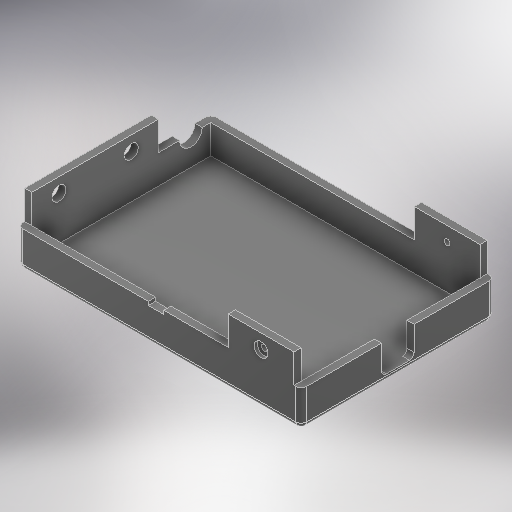
# Autodesk Inventor part: top_casing
Saved by Autodesk Inventor 2027 (Build 310192060, 192F)
## iProperties
Created: 2026-09-12
Part Number: top_casing
Material: Generic
Document SubType Name: Modeling
Designer: Aiden
Density: 1 g/cm^3
Appearance: Smooth - Black
Author: Aiden
Autodesk Inventor part; units mm, degrees
ref_plane "YZ Plane" through (0, 0, 0) normal (1, 0, 0) x (0, 1, 0)
ref_plane "XZ Plane" through (0, 0, 0) normal (0, 1, 0) x (-1, 0, 0)
ref_plane "XY Plane" through (0, 0, 0) normal (0, 0, 1) x (1, 0, 0)
sketch "Sketch1" plane through (0, 0, 0) normal (0, 1, 0) x (-1, 0, 0)
  line L0 (0, 0) -> (54.318, 0)
  line L1 (54.318, 0) -> (54.318, -54.318)
  line L2 (54.318, -54.318) -> (0, -54.318)
  line L3 (0, -54.318) -> (0, 0)
  line L4 (54.318, 0) -> (79.718, 0)
  line L5 (79.718, 0) -> (79.718, -54.318)
  line L6 (79.718, -54.318) -> (54.318, -54.318)
  line L7 (54.318, -54.318) -> (54.318, 0)
  dimension "d0" = 54.318
  dimension "d1" = 54.318
  dimension "d2" = 25.4
  constraints: 16 end point, 4 parallel, 2 horizontal, 2 perpendicular
  measures "d0" distance of L0.end L1.end
  measures "d1" distance of L1.end L2.end
  measures "d2" distance of L5.end L6.end
extrude "Extrusion1" add sketch "Sketch1" along normal blind 10.16
sketch "Sketch2" plane through (0, 10.16, 0) normal (0, 1, 0) x (1, 0, 0)
  line L0 (-77.686, 52.286) -> (-2.032, 52.286)
  line L1 (-2.032, 52.286) -> (-2.032, 2.032)
  line L2 (-2.032, 2.032) -> (-77.686, 2.032)
  line L3 (-77.686, 2.032) -> (-77.686, 52.286)
  line L4 (-77.686, 52.286) -> (-77.686, 54.318) construction
  line L5 (0, 54.318) -> (-79.718, 54.318) construction
  line L6 (-2.032, 52.286) -> (0, 52.286) construction
  line L7 (-2.032, 2.032) -> (-2.032, 0) construction
  line L8 (-79.718, 0) -> (0, 0) construction
  line L9 (-77.686, 2.032) -> (-79.718, 2.032) construction
  line L10 (-79.718, 54.318) -> (-79.718, 0) construction
  line L11 (0, 0) -> (0, 54.318) construction
  dimension "d5" = 2.032
  constraints: 16 end point, 6 perpendicular, 4 point on line, 2 parallel, 2 vertical, 1 horizontal
  measures "d5" distance of L0.start L4.end
extrude "Extrusion2" cut sketch "Sketch2" against normal blind 8.128
sketch "Sketch3" plane through (0, 10.16, 0) normal (0, 1, 0) x (1, 0, 0)
  line L0 (-2.032, 2.032) -> (-77.686, 2.032) projected
  line L1 (-79.718, 0) -> (0, 0) projected
  line L2 (-42.926, 2.032) -> (-38.608, 2.032)
  line L3 (-38.608, 2.032) -> (-38.608, 0)
  line L4 (-38.608, 0) -> (-42.926, 0)
  line L5 (-42.926, 0) -> (-42.926, 2.032)
  line L6 (0, 0) -> (0, 54.318) projected
  point P0 (-38.608, 1.016)
  dimension "d8" = 4.318
  dimension "d9" = 38.608
  constraints: 8 end point, 2 parallel, 2 point on line, 1 horizontal, 1 midpoint, 1 perpendicular
  measures "d8" distance from line of point (-38.608, 1.016) L5
  measures "d9" distance between parallel lines of L6 L3
extrude "Extrusion3" cut sketch "Sketch3" against normal blind 1.016
sketch "Sketch4" plane through (-79.718, 0, -54.318) normal (-1, 0, 0) x (0, 0, 1)
  circle A0 centre (7.62, 10.16) radius 3.175
  line L0 (0, 0) -> (0, 10.16) projected
  line L1 (0, 10.16) -> (54.318, 10.16) projected
  point P0 (54.318, 0)
  dimension "d12" = 6.35
  dimension "d13" = 7.62
  constraints: 1 centre point, 1 point on line
  measures "d12" diameter of A0
  measures "d13" distance from line of L0 A0.centre
extrude "Extrusion4" cut sketch "Sketch4" against normal blind 2.032
sketch "Sketch5" plane through (0, 10.16, 0) normal (0, 1, 0) x (1, 0, 0)
  line L0 (-42.926, 2.032) -> (-77.686, 2.032) projected
  line L1 (-79.718, 43.523) -> (-79.718, 0) projected
  line L2 (-77.686, 2.032) -> (-79.718, 2.032)
  line L3 (-79.718, 2.032) -> (-79.718, 37.592)
  line L4 (-79.718, 37.592) -> (-77.686, 37.592)
  line L5 (-77.686, 37.592) -> (-77.686, 2.032)
  point P0 (0, 0)
  dimension "d16" = 35.56
  constraints: 8 end point, 2 parallel, 1 horizontal, 1 perpendicular, 1 point on line
  measures "d16" distance between parallel lines of L2 L4
extrude "Extrusion5" add sketch "Sketch5" along normal blind 8.128
sketch "Sketch6" plane through (-79.718, 0, -54.318) normal (-1, 0, 0) x (0, 0, 1)
  line L0 (16.726, 18.288) -> (52.286, 18.288) projected
  line L1 (54.318, 10.16) -> (0, 10.16) projected
  line L2 (21.806, 18.288) -> (26.886, 18.288)
  line L3 (26.886, 18.288) -> (26.886, 10.16)
  line L4 (26.886, 10.16) -> (21.806, 10.16)
  line L5 (21.806, 10.16) -> (21.806, 18.288)
  line L6 (42.126, 10.16) -> (47.206, 10.16)
  line L7 (47.206, 10.16) -> (47.206, 18.288)
  line L8 (47.206, 18.288) -> (42.126, 18.288)
  line L9 (42.126, 18.288) -> (42.126, 10.16)
  line L10 (21.806, 14.224) -> (26.886, 14.224) construction
  line L11 (42.126, 14.224) -> (47.206, 14.224) construction
  line L12 (16.726, 10.16) -> (16.726, 18.288) construction
  line L13 (24.346, 18.288) -> (24.346, 10.16) construction
  line L14 (44.666, 10.16) -> (44.666, 18.288) construction
  line L15 (52.286, 10.16) -> (52.286, 18.288) construction
  circle A0 centre (24.346, 14.224) radius 1.95
  circle A1 centre (44.666, 14.224) radius 1.95
  point P0 (54.318, 0)
  dimension "d19" = 5.08
  dimension "d20" = 5.08
  dimension "d21" = 5.08
  dimension "d22" = 3.9
  constraints: 24 end point, 10 midpoint, 4 parallel, 4 point on line, 2 centre point, 2 horizontal, 2 perpendicular, 1 collinear, 1 equal radius
  measures "d19" distance of L10.start L10.end
  measures "d20" distance between parallel lines of L12 L5
  measures "d21" distance between parallel lines of L15 L7
  measures "d22" diameter of A0
extrude "Extrusion6" cut sketch "Sketch6" against normal blind 2.032 contours A0 | A1
sketch "Sketch7" plane through (0, 10.16, 0) normal (0, 1, 0) x (1, 0, 0)
  line L0 (-2.032, 2.032) -> (-77.686, 2.032) projected
  line L1 (-79.718, 0) -> (0, 0) projected
  line L2 (-20.5232, 2.032) -> (-2.032, 2.032)
  line L3 (-2.032, 2.032) -> (-2.032, 0)
  line L4 (-2.032, 0) -> (-20.5232, 0)
  line L5 (-20.5232, 0) -> (-20.5232, 2.032)
  line L6 (-77.686, 52.286) -> (-2.032, 52.286) projected
  line L7 (0, 54.318) -> (-79.718, 54.318) projected
  line L8 (-2.032, 52.286) -> (-20.5232, 52.286)
  line L9 (-20.5232, 52.286) -> (-20.5232, 54.318)
  line L10 (-20.5232, 54.318) -> (-2.032, 54.318)
  line L11 (-2.032, 54.318) -> (-2.032, 52.286)
  line L12 (0, 0) -> (0, 54.318) projected
  line L13 (-2.032, 1.016) -> (-20.5232, 1.016) construction
  line L14 (-2.032, 53.302) -> (-20.5232, 53.302) construction
  point P0 (-20.5232, 0)
  dimension "d25" = 2.032
  dimension "d26" = 2.032
  dimension "d27" = 18.4912
  constraints: 20 end point, 5 parallel, 4 midpoint, 4 point on line, 2 horizontal, 2 perpendicular
  measures "d25" distance between parallel lines of L12 L3
  measures "d26" distance between parallel lines of L12 L11
  measures "d27" distance of L13.start L13.end
extrude "Extrusion7" add sketch "Sketch7" along normal blind 8.128
sketch "Sketch8" plane through (-79.718, 0, 0) normal (0, 0, 1) x (1, 0, 0)
  line L0 (59.1948, 18.288) -> (77.686, 18.288) construction
  line L1 (59.1948, 10.16) -> (59.1948, 18.288) construction
  line L2 (77.686, 10.16) -> (77.686, 18.288) construction
  circle A0 centre (68.4404, 14.224) radius 1.95
  line L3 (59.1948, 14.224) -> (77.686, 14.224) construction
  line L4 (68.4404, 18.288) -> (68.4404, 5.811) construction
  point P0 (79.718, 0)
  point P1 (68.4404, 14.224)
  dimension "d30" = 3.9
  constraints: 4 end point, 4 midpoint, 2 coincident, 1 centre point, 1 vertical
  measures "d30" diameter of A0
extrude "Extrusion8" cut sketch "Sketch8" against normal blind 2.032
sketch "Sketch9" plane through (0, 0, -54.318) normal (0, 0, -1) x (-1, 0, 0)
  circle A0 centre (11.2776, 14.224) radius 1.95 projected
  point P0 (0, 0)
extrude "Extrusion9" cut sketch "Sketch9" against normal blind 2.032
fillet "Fillet1" radius 1.524 4 edges at (-79.718, 5.08, -54.318) (0, 5.08, -54.318) (0, 5.08, 0) (-79.718, 5.08, 0)
fillet "Fillet2" radius 1.524 8 edges at (-0.4464, 0, -0.4464) (0, 0, -27.159) (-0.4464, 0, -53.8716) (-39.859, 0, -54.318) (-79.2716, 0, -53.8716) (-79.718, 0, -27.159) (-79.2716, 0, -0.4464) (-39.859, 0, 0)
sketch "Sketch10" plane through (0, 10.16, -1.524) normal (1, 0, 0) x (0, 0, -1)
  line L0 (30.207, -8.128) -> (21.063, -8.128)
  line L1 (21.063, -8.128) -> (21.063, -4.826)
  line L2 (21.063, -4.826) -> (30.207, -4.826)
  line L3 (30.207, -4.826) -> (30.207, -8.128)
  line L4 (51.27, -10.16) -> (0, -10.16) construction
  line L5 (50.762, 0) -> (0.508, 0) construction
  line L6 (25.635, -10.16) -> (25.635, 0) construction
  line L7 (30.207, -4.826) -> (21.063, -4.826)
  line L8 (21.063, -4.826) -> (21.063, 0)
  line L9 (21.063, 0) -> (30.207, 0)
  line L10 (30.207, 0) -> (30.207, -4.826)
  point P0 (-1.524, -10.16)
  point P1 (25.635, -8.128)
  dimension "d37" = 2.032
  dimension "d40" = 9.144
  dimension "d41" = 3.302
  constraints: 18 end point, 4 parallel, 3 midpoint, 2 horizontal, 2 perpendicular, 2 point on line
  measures "d37" distance between parallel lines of L4 L0
  measures "d40" distance of L1.end L2.end
  measures "d41" distance of L0.end L1.end
extrude "Extrusion10" cut sketch "Sketch10" against normal blind 2.032
fillet "Fillet3" radius 1.27 2 edges at (-1.016, 2.032, -31.731) (-1.016, 2.032, -22.587)
sketch "Sketch11" plane through (-2.032, 2.032, -2.032) normal (0, 0, -1) x (-1, 0, 0)
  circle A0 centre (9.2456, 12.192) radius 1.95 projected
  circle A1 centre (9.2456, 12.192) radius 0.825
  point P0 (-2.032, -2.032)
  dimension "d46" = 1.65
  constraints: 1 centre point, 1 coincident
  measures "d46" diameter of A1
extrude "Extrusion11" add sketch "Sketch11" against normal blind 1.1176
sketch "Sketch12" plane through (-77.686, 2.032, -52.286) normal (0, 0, 1) x (1, 0, 0)
  circle A0 centre (66.4084, 12.192) radius 1.95 projected
  circle A1 centre (66.4084, 12.192) radius 0.825
  point P0 (77.686, -2.032)
  dimension "d47" = 1.65
  constraints: 1 centre point, 1 coincident
  measures "d47" diameter of A1
extrude "Extrusion12" add sketch "Sketch12" against normal blind 1.1176
body "Solid1"
